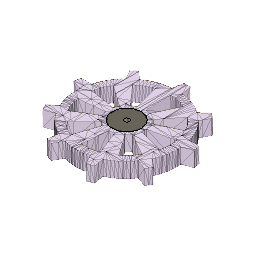
hex wheel (Autodesk Fusion 360 design; units mm, degrees)
part number: 2026-10-27-13-51-46-542
Autodesk Fusion 360 part; units mm, degrees
other "Base Mesh Feature1"
sketch "Sketch1" plane through (0, 0, 0) normal (0, 0, 1) x (1, 0, 0)
other "Scale1"
sketch "Sketch2" plane through (0, 0, 0) normal (0, 0, 1) x (1, 0, 0)
  line L0 (-3.6373, 6.3) -> (-7.2746, 0)
  line L1 (-7.2746, 0) -> (-3.6373, -6.3)
  line L2 (-3.6373, -6.3) -> (3.6373, -6.3)
  line L3 (3.6373, -6.3) -> (7.2746, 0)
  line L4 (7.2746, 0) -> (3.6373, 6.3)
  line L5 (3.6373, 6.3) -> (-3.6373, 6.3)
  circle A0 centre (0, 0) radius 11.4314
  dimension "d2" = 6.3
  constraint coincident A0.centre origin
  measures "d2" distance of A0.centre L5
extrude "Extrude1" add sketch "Sketch2" along normal blind 12
sketch "Sketch3" plane through (0, 0, 12) normal (0, 0, 1) x (-1, 0, 0)
  line L0 (3.6373, -6.3) -> (-3.6373, -6.3)
  line L1 (-3.6373, -6.3) -> (-7.2746, 0)
  line L2 (-7.2746, 0) -> (-3.6373, 6.3)
  line L3 (-3.6373, 6.3) -> (3.6373, 6.3)
  line L4 (3.6373, 6.3) -> (7.2746, 0)
  line L5 (7.2746, 0) -> (3.6373, -6.3)
  circle A0 centre (0, 0) radius 11.4314
  circle A1 centre (0, 0) radius 11.4314
  constraint coincident A0.centre A1.centre
extrude "Extrude2" add sketch "Sketch3" against normal blind 6 contours L0 L1 L2 L3 L4 L5
sketch "Sketch4" plane through (0, 0, 12) normal (0, 0, 1) x (-1, 0, 0)
  circle A0 centre (0, 0) radius 11.4314
  circle A1 centre (0, 0) radius 2
  dimension "d7" = 4
  constraint coincident A0.centre A1.centre
  measures "d7" diameter of A1
extrude "Extrude3" cut sketch "Sketch4" against normal through all contours A1
